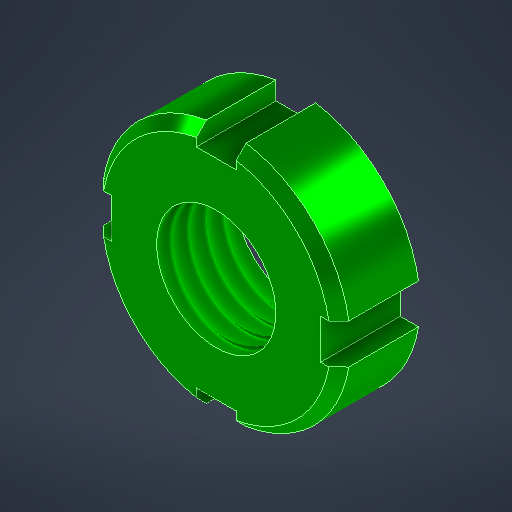
# Autodesk Inventor part: 7. Lock Nut M12
Saved by Autodesk Inventor 2025.2 (Build 292293000, 293)
## iProperties
Created: 2025-05-09
Part Number: 7. Lock Nut M12
Material: Steel, Mild
Document SubType Name: Modeling
Designer: trysm
Density: 7.85 g/cm^3
Appearance: Semi-Polished
Author: trysm
Autodesk Inventor part; units mm, degrees
ref_plane "YZ Plane" through (0, 0, 0) normal (1, 0, 0) x (0, 1, 0)
ref_plane "XZ Plane" through (0, 0, 0) normal (0, 1, 0) x (-1, 0, 0)
ref_plane "XY Plane" through (0, 0, 0) normal (0, 0, 1) x (1, 0, 0)
sketch "Sketch1" plane through (0, 0, 0) normal (0, 1, 0) x (-1, 0, 0)
  circle A0 centre (0, 0) radius 6
  circle A1 centre (0, 0) radius 12.5
  line L0 (2, 14.5) -> (-2, 14.5)
  line L1 (-2, 14.5) -> (-2, 10.5)
  line L2 (-2, 10.5) -> (2, 10.5)
  line L3 (2, 10.5) -> (2, 14.5)
  line L4 (2, 14.5) -> (-2, 10.5) construction
  line L5 (-2, 14.5) -> (2, 10.5) construction
  line L6 (-14.5, 2) -> (-14.5, -2)
  line L7 (-14.5, -2) -> (-10.5, -2)
  line L8 (-10.5, -2) -> (-10.5, 2)
  line L9 (-10.5, 2) -> (-14.5, 2)
  line L10 (-14.5, 2) -> (-10.5, -2) construction
  line L11 (-14.5, -2) -> (-10.5, 2) construction
  line L12 (-2, -14.5) -> (2, -14.5)
  line L13 (2, -14.5) -> (2, -10.5)
  line L14 (2, -10.5) -> (-2, -10.5)
  line L15 (-2, -10.5) -> (-2, -14.5)
  line L16 (-2, -14.5) -> (2, -10.5) construction
  line L17 (2, -14.5) -> (-2, -10.5) construction
  line L18 (14.5, -2) -> (14.5, 2)
  line L19 (14.5, 2) -> (10.5, 2)
  line L20 (10.5, 2) -> (10.5, -2)
  line L21 (10.5, -2) -> (14.5, -2)
  line L22 (14.5, -2) -> (10.5, 2) construction
  line L23 (14.5, 2) -> (10.5, -2) construction
  point P0 (0, 12.5)
  point P1 (-12.5, 0)
  point P2 (0, -12.5)
  point P3 (12.5, 0)
  point P4 (-2, 12.339)
  point P5 (-12.339, 2)
  point P6 (-12.339, -2)
  point P7 (-2, -12.339)
  point P8 (2, -12.339)
  point P9 (12.339, -2)
  point P10 (12.339, 2)
  point P11 (2, 12.339)
  dimension "d39" = 25
  dimension "d38" = 12
  dimension "d40" = 4
  dimension "d41" = 4
  dimension "d44" = 360
  constraints: 48 end point, 2 coincident, 2 midpoint, 2 parallel, 1 centre point, 1 horizontal, 1 perpendicular, 1 vertical alignment, 48 other
  measures "d38" diameter of A0
  measures "d40" distance of L1.end L0.end
  measures "d41" distance of L1.end L2.end
extrude "Extrusion1" add sketch "Sketch1" along normal blind 8 contours L19 L20 L21 A1 L13 L14 L15 L7 L8 L9 L1 L2 L3
chamfer "Chamfer3" distance 1 angle 45 4 edges at (-8.8388, 0, 8.8388) (8.8388, 0, 8.8388) (-8.8388, 0, -8.8388) (8.8388, 0, -8.8388)
thread "Thread3" size "M12x1.75" class "6H" standard "ANSI Metric M Profile" full length
body "Solid1"
